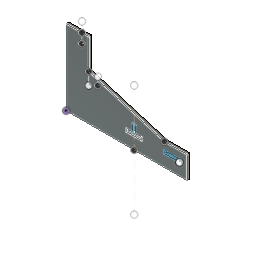
BASE (Autodesk Fusion 360 design; units mm, degrees)
part number: 2026-06-03-16-48-55-168
Autodesk Fusion 360 part; units mm, degrees
sketch "Sketch1" plane through (0, -198, 0) normal (0, -1, 0) x (1, 0, 0)
  circle A0 centre (94.7339, 114.4362) radius 4
  circle A1 centre (50, 195) radius 4
  line L0 (100, 120.0119) -> (100, 210)
  line L1 (100, 210) -> (0, 210)
  line L2 (0, 210) -> (0, 0)
  line L3 (0, 0) -> (500, 0)
  line L4 (500, 0) -> (500, 60)
  line L5 (500, 60) -> (404.1283, 59.9621)
  line L6 (404.1283, 59.9621) -> (100, 120.0119)
  line L7 (210, 40) -> (250, 40)
  line L8 (250, 40) -> (250, 50)
  line L9 (210, 50) -> (210, 40)
  line L10 (235, 70) -> (225, 70)
  line L11 (225, 70) -> (225, 50)
  line L12 (225, 20) -> (235, 20)
  line L13 (235, 50) -> (235, 70)
  line L14 (235, 70) -> (229, 40) construction
  line L15 (250, 50) -> (235, 50)
  line L16 (225, 50) -> (210, 50)
  line L17 (225, 70) -> (229, 50) construction
  line L18 (230, 45) -> (231, 40) construction
  dimension "d1" = 10
  dimension "d8" = 500
  dimension "d9" = 210
  constraint horizontal L7
  constraint vertical L8
  constraint horizontal L15
  constraint vertical L9
  constraint horizontal L10
  constraint perpendicular L10 L11
  constraint parallel L10 L12
  constraint parallel L11 L13
  constraint coincident L14 L18.start
  constraint coincident L7 L18.end
  constraint coincident L7 L14.end
  constraint collinear L15 L16
  constraint collinear L17 L18
  measures "d1" distance of L12.start L12.end
  measures "d8" distance of L2.end L3.end
  measures "d9" distance of L1.end L2.end
sketch "Sketch2" plane through (0, -198, 0) normal (0, -1, 0) x (1, 0, 0)
  line L0 (0, 0) -> (500, 0)
  line L1 (500, 0) -> (500, 60)
  line L2 (100, 210) -> (0, 210)
  line L3 (0, 210) -> (0, 0)
  line L4 (100, 210) -> (100, 120)
  line L5 (100, 120) -> (404, 60)
  line L6 (404, 60) -> (500, 60)
  circle A0 centre (50, 195) radius 4
  circle A1 centre (135, 105) radius 4
  dimension "d2" = 8
  dimension "d3" = 8
  constraint horizontal L0
  constraint vertical L1
  constraint horizontal L2
  constraint vertical L3
  constraint coincident L0.start L3.end
  constraint perpendicular L2 L4
  constraint perpendicular L1 L6
  measures "d2" diameter of A0
  measures "d3" diameter of A1
sketch "Sketch3" plane through (0, 0, 0) normal (0, 1, 0) x (1, 0, 0)
  line L0 (0, 0) -> (800, 0)
  line L1 (800, 0) -> (800, -150)
  line L2 (150, -500) -> (0, -500)
  line L3 (0, -500) -> (0, 0)
  line L4 (150, -300) -> (150, -500)
  line L5 (150, -300) -> (650, -150)
  line L6 (650, -150) -> (800, -150)
  line L7 (105, -564.1027) -> (105, -435.8973) construction
  circle A0 centre (105, -437.2) radius 5
  circle A1 centre (210, -249.9232) radius 5
  line L8 (150, -300) -> (150, -220) construction
  line L9 (210, -249.9232) -> (210, -282) construction
  line L10 (150, -300) -> (210, -300) construction
  line L11 (450, 370) -> (450, -370) construction
  line L12 (400, -99) -> (400, -80)
  line L13 (400, -80) -> (500, -80)
  line L14 (500, -80) -> (500, -99)
  line L15 (440.5912, -99) -> (440.5912, -149)
  line L16 (440.5912, -149) -> (459.5912, -149)
  line L17 (459.5912, -149) -> (459.5912, -99)
  line L18 (500, -99) -> (459.5912, -99)
  line L19 (440.5912, -99) -> (400, -99)
  line L20 (750, -80) -> (750, -99)
  line L21 (650, -80) -> (750, -80)
  line L22 (650, -99) -> (750, -99)
  line L23 (650, -99) -> (650, -80)
  point P0 (150, -300)
  point P1 (650, -150)
  point P2 (105, -500)
  point P3 (450, 0)
  dimension "d10" = 800
  dimension "d11" = 500
  dimension "d12" = 150
  dimension "d13" = 200
  dimension "d14" = 150
  dimension "d15" = 150
  dimension "d16" = 300
  dimension "d17" = 150
  dimension "d18" = 10
  dimension "d19" = 45
  dimension "d20" = 62.8
  dimension "d21" = 10
  dimension "d22" = 60
  dimension "d25" = 300
  dimension "d26" = 80
  dimension "d27" = 19
  dimension "d28" = 100
  dimension "d29" = 19
  dimension "d30" = 50
  dimension "d35" = 19
  dimension "d40" = 100
  dimension "d41" = 150
  constraint horizontal L0
  constraint vertical L1
  constraint horizontal L2
  constraint vertical L3
  constraint coincident L0.start L3.end
  constraint coincident P0 L4.start
  constraint coincident L2.start L4.end
  constraint perpendicular L2 L4
  constraint coincident P1 L5.end
  constraint coincident L1.end L6.end
  constraint perpendicular L1 L6
  constraint midpoint L7 P2
  constraint coincident L2 P2
  constraint perpendicular L2 L7
  constraint coincident L7 A0.centre
  constraint parallel L4 L8
  constraint coincident A1.centre L9.start
  constraint coincident L5 L9.end
  constraint vertical L9
  constraint perpendicular L8 L10
  constraint midpoint L11 P3
  constraint coincident L0 P3
  constraint perpendicular L0 L11
  constraint horizontal L18
  constraint perpendicular L12 L19
  constraint parallel L13 L18
  constraint parallel L12 L14
  constraint perpendicular L15 L19
  constraint perpendicular L15 L16
  constraint perpendicular L17 L18
  constraint collinear L18 L19
  constraint perpendicular L20 L22
  constraint perpendicular L21 L23
  measures "d10" distance of L0.start L0.end
  measures "d11" distance of L0.start L2.end
  measures "d12" distance of L2.end L2.start
  measures "d13" distance of L2.start P0
  measures "d14" distance of L0.end L1.end
  measures "d15" distance of L1.end P1
  measures "d16" distance of L0 P0
  measures "d17" distance of L0 P1
  measures "d18" diameter of A0
  measures "d19" distance of L4 A0.centre
  measures "d20" distance of L2 A0.centre
  measures "d21" diameter of A1
  measures "d22" distance of A1.centre L8
  measures "d25" distance of L1 L14
  measures "d26" distance of L0 L13
  measures "d27" distance of L14.end L13.end
  measures "d28" distance of L12.end L13.end
  measures "d29" distance of L15.end L16.end
  measures "d30" distance of L16.end L17.end
  measures "d35" distance of L20.end L20.start
  measures "d40" distance of L21.start L20.start
  measures "d41" distance of L13.end L21.start
extrude "Extrude4" add sketch "Sketch3" along normal blind 18
